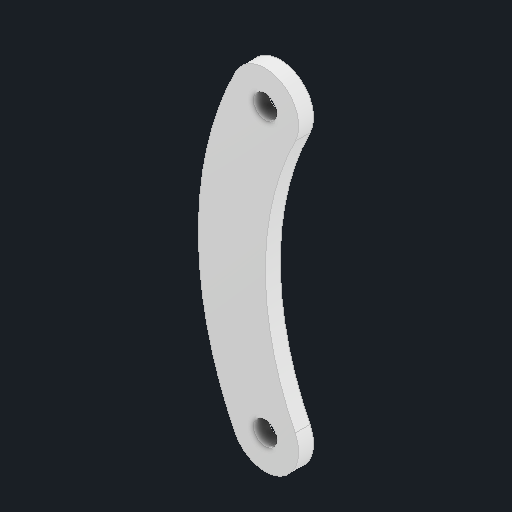
# Autodesk Inventor part: Diag
Saved by Autodesk Inventor 2026 (Build 300175050, 175E)
## iProperties
Created: 2025-10-23
Part Number: Diag
Material: Plástico ABS
Document SubType Name: Modeling
Designer: thepr
Density: 1.06 g/cm^3
Appearance: Suave - Blanco
Author: thepr
Autodesk Inventor part; units mm, degrees
ref_plane "YZ Plane" through (0, 0, 0) normal (1, 0, 0) x (0, 1, 0)
ref_plane "XZ Plane" through (0, 0, 0) normal (0, 1, 0) x (-1, 0, 0)
ref_plane "XY Plane" through (0, 0, 0) normal (0, 0, 1) x (1, 0, 0)
sketch "Boceto1" plane through (0, 0, 0) normal (0, 0, 1) x (1, 0, 0)
  line L0 (0, 0) -> (0, 38) construction
  line L1 (4.5, 0) -> (4.5, 38)
  line L2 (-4.5, 38) -> (-4.5, 0)
  arc A0 (-4.5, 0) -> (4.5, 0) centre (0, 0) ccw
  arc A1 (4.5, 38) -> (-4.5, 38) centre (0, 38) ccw
  circle A2 centre (0, 38) radius 2.5
  circle A3 centre (0, 0) radius 2.5
  point P0 (0, 19)
  point P1 (0, 42.5)
  point P2 (0, -4.5)
  dimension "d0" = 38
  dimension "d1" = 9
  dimension "d2" = 5
  dimension "d3" = 5
  dimension "d6" = 47
  constraints: 8 end point, 6 point on circle, 4 centre point, 4 tangent, 2 coincident, 1 midpoint, 1 parallel, 1 vertical
  measures "d0" distance of L0.start L0.end
  measures "d1" diameter of A1
  measures "d2" diameter of A2
  measures "d3" diameter of A3
  measures "d6" distance of point (0, 42.5) point (0, -4.5)
extrude "Extrusión1" add sketch "Boceto1" along normal blind 2
sketch "Boceto2" plane through (0, 0, 2) normal (0, 0, 1) x (1, 0, 0)
  arc A0 (4.5, 38) -> (-4.5, 38) centre (0, 38) ccw projected
  line L0 (-4.5, 38) -> (-4.5, 0) projected
  arc A1 (-4.5, 0) -> (4.5, 0) centre (0, 0) ccw projected
  line L1 (4.5, 0) -> (4.5, 38) projected
  circle A2 centre (0, 0) radius 2.5 projected
  circle A3 centre (0, 38) radius 2.5 projected
  circle A4 centre (0, 0) radius 1.6
  circle A5 centre (0, 38) radius 1.6
  dimension "d7" = 3.2
  dimension "d8" = 3.2
  constraints: 2 centre point, 2 coincident
  measures "d7" diameter of A5
  measures "d8" diameter of A4
extrude "Extrusión2" add sketch "Boceto2" against normal blind 2 contours A2 | A3
sketch "Boceto3" plane through (0, 0, 0) normal (0, 0, -1) x (-1, 0, 0)
  arc A0 (4.5, 38) -> (-4.5, 38) centre (0, 38) ccw projected
  arc A1 (-4.5, 0) -> (4.5, 0) centre (0, 0) ccw projected
  arc A2 (-4.0253, 40.0118) -> (-4.0253, -2.0118) centre (38.0164, 19) ccw
  arc A3 (-4.5, 0) -> (4.5, 0) centre (0, 0) ccw projected
  arc A4 (4.5, 38) -> (-4.5, 38) centre (0, 38) ccw projected
  circle A5 centre (0, 38) radius 1.6 projected
  circle A6 centre (0, 38) radius 4.5
  circle A7 centre (0, 0) radius 1.6 projected
  circle A8 centre (0, 0) radius 4.5
  arc A9 (4.0253, 35.9882) -> (4.0253, 2.0118) centre (38.0164, 19) ccw
  circle A10 centre (0, 0) radius 1.6 projected
  circle A11 centre (0, 38) radius 1.6 projected
  arc A12 (4.5, 38) -> (-4.5, 38) centre (0, 38) ccw projected
  line L0 (-4.5, 0) -> (-4.5, 38) projected
  arc A13 (-4.5, 0) -> (4.5, 0) centre (0, 0) ccw projected
  line L1 (4.5, 38) -> (4.5, 0) projected
  circle A14 centre (0, 0) radius 1.6 projected
  line L2 (0, 0) -> (0, 38)
  arc A15 (4.0253, -2.0118) -> (4.0253, 40.0118) centre (-38.0164, 19) ccw
  arc A16 (-4.0253, 2.0118) -> (-4.0253, 35.9882) centre (-38.0164, 19) ccw
  point P0 (-4.5, 13.9964)
  point P1 (-4.5, 24.0036)
  point P2 (4.5, 0)
  point P3 (4.5, 24.0036)
  point P4 (4.5, 13.9964)
  point P5 (4.5, 0)
  point P6 (4.0253, -2.0118)
  point P7 (4.0253, 40.0118)
  point P8 (-2.9734, 3.3777)
  point P9 (-2.9734, 34.6223)
  point P10 (-4.0253, 2.0118)
  point P11 (-4.0253, 35.9882)
  point P12 (4.0253, -2.0118)
  point P13 (4.0253, 40.0118)
  dimension "d23" = 47
  dimension "d24" = 0
  constraints: 12 point on circle, 6 symmetric about line, 5 centre point, 3 tangent, 2 coincident, 2 end point, 1 vertical, 7 other
  measures "d23" radius of A2
  measures "d24" distance of A15.centre A16.centre
extrude "Extrusión3" add sketch "Boceto3" against normal up to surface (2 mm away) contours A0 A15 A1 L1
extrude "Extrusión5" cut sketch "Boceto3" against normal blind 11.25 contours A6 A16 A8 L0
sketch "Boceto4" plane through (0, 0, 2) normal (0, 0, 1) x (1, 0, 0)
  circle A0 centre (0, 0) radius 1.6 projected
  circle A1 centre (0, 0) radius 1.9
  dimension "d25" = 3.8
  constraints: 1 centre point, 1 coincident
  measures "d25" diameter of A1
extrude "Extrusión6" [suppressed]
